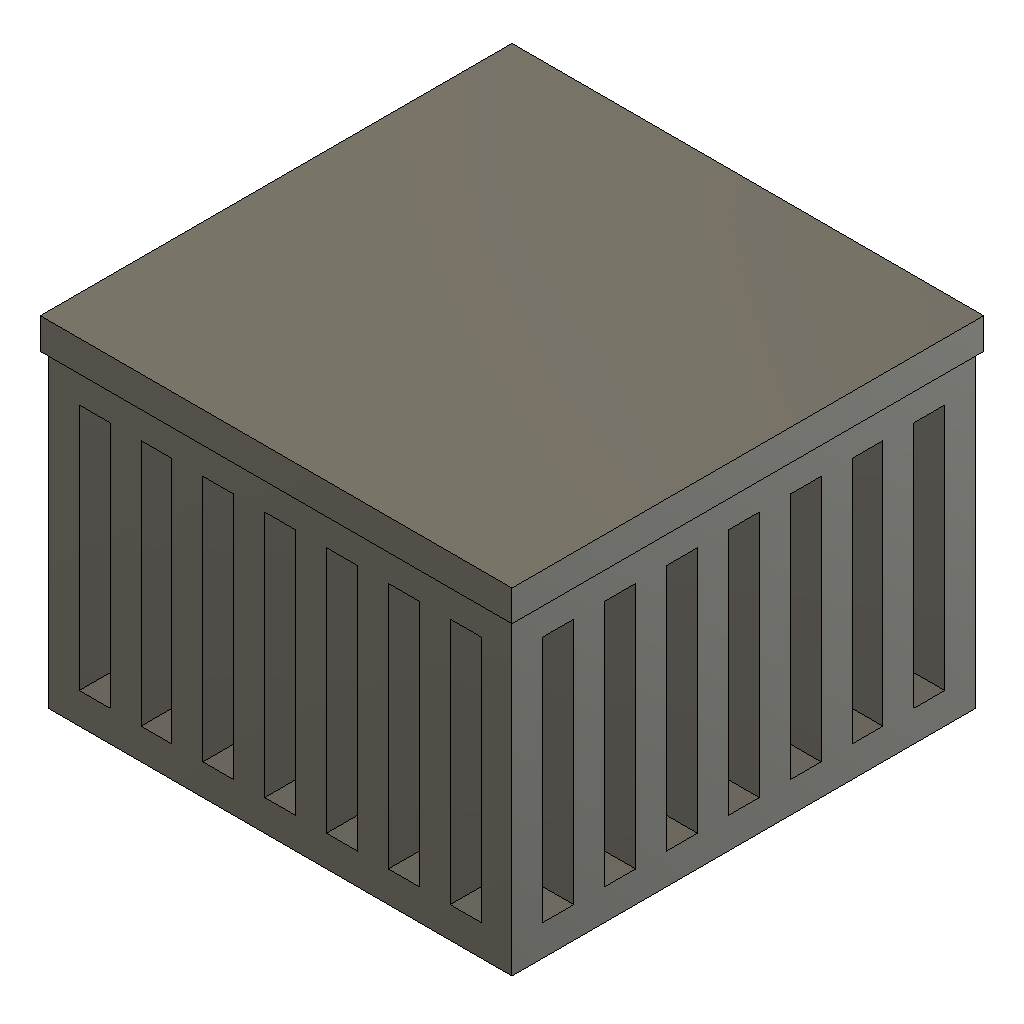
box (Autodesk Fusion 360 design; units mm, degrees)
part number: 2026-11-11-17-09-07-417
Autodesk Fusion 360 part; units mm, degrees
sketch "Sketch1" plane through (0, 0, 0) normal (0, 1, 0) x (1, 0, 0)
  line L0 (0, 0) -> (-150, 0)
  line L1 (-150, 0) -> (-150, 150)
  line L2 (-150, 150) -> (0, 150)
  line L3 (0, 150) -> (0, 0)
  dimension "d1" = 150
  dimension "d2" = 150
  constraint horizontal L0
  constraint vertical L1
  constraint horizontal L2
  constraint vertical L3
  constraint coincident L0.start L3.end
  measures "d1" distance of L0.start L0.end
  measures "d2" distance of L0.start L2.end
extrude "Extrude1" add sketch "Sketch1" along normal blind 100 makes body 1
sketch "Sketch2" plane through (0, 0, -150) normal (0, 0, -1) x (-1, 0, 0)
  line L0 (0, 0) -> (150, 0)
  line L1 (150, 0) -> (150, 100)
  line L2 (150, 100) -> (0, 100)
  line L3 (0, 100) -> (0, 0)
  line L4 (0, 100) -> (150, 100)
  line L5 (150, 100) -> (150, 0)
  line L6 (150, 0) -> (0, 0)
  line L7 (0, 0) -> (0, 100)
  line L8 (140, 10) -> (10, 10)
  line L9 (10, 10) -> (10, 90)
  line L10 (10, 90) -> (140, 90)
  line L11 (140, 90) -> (140, 10)
  line L12 (10, 90) -> (20, 90)
  line L13 (20, 90) -> (20, 10)
  line L14 (20, 10) -> (10, 10)
  line L15 (10, 10) -> (10, 90)
  constraint horizontal L4
  constraint vertical L5
  constraint horizontal L6
  constraint vertical L7
  constraint coincident L0.end L1.start
  constraint coincident L2.end L3.start
  constraint horizontal L8
  constraint vertical L9
  constraint horizontal L10
  constraint vertical L11
  constraint horizontal L12
  constraint vertical L13
  constraint horizontal L14
  constraint vertical L15
  constraint coincident L8 L13.end
extrude "Extrude2" add sketch "Sketch2" along normal blind 5 separate body contours L8 L9 L10 L12 L13 L14 L15 makes body 2
chamfer "Chamfer1" distance 5 angle 45 1 faces at (-13.3333, 36.6667, -155) tangent chain off on bodies 2
move_body "Move1" bodies 2 to x (-1, 0, 0) y (0, 1, 0) z (0, 0, -1) at (-30, 0, -310)
copy_body "CopyPasteBodies1" bodies 2 makes body 3
move_body "Move2" bodies 3 to x (1, 0, 0) y (0, 1, 0) z (0, 0, 1) at (-20, 0, 0)
copy_body "CopyPasteBodies2" bodies 2 3 makes body 4 makes body 5
move_body "Move3" bodies 4 5 to x (1, 0, 0) y (0, 1, 0) z (0, 0, 1) at (-40, 0, 0)
copy_body "CopyPasteBodies3" bodies 2 3 5 4 makes body 6 makes body 7 makes body 8 makes body 9
move_body "Move4" bodies 6 7 8 9 to x (1, 0, 0) y (0, 1, 0) z (0, 0, 1) at (-80, 0, 0)
delete_body "RemoveBody1" bodies 8
move_body "Move5" bodies 2 7 6 9 3 5 4 to x (1, 0, 0) y (0, 1, 0) z (0, 0, 1) at (0, 0, 10)
copy_body "CopyPasteBodies4" bodies 2 7 6 9 3 5 4 makes body 10 makes body 11 makes body 12 makes body 13 makes body 14 makes body 15 makes body 16
move_body "Move6" bodies 10 11 12 13 14 15 16 to x (0, 0, -1) y (0, 1, 0) z (1, 0, 0) at (0, 0, -150)
copy_body "CopyPasteBodies5" bodies 2 7 6 9 3 5 4 makes body 17 makes body 18 makes body 19 makes body 20 makes body 21 makes body 22 makes body 23
move_body "Move7" bodies 17 18 19 20 21 22 23 to x (-1, 0, 0) y (0, 1, 0) z (0, 0, -1) at (-150, 0, -150)
copy_body "CopyPasteBodies6" bodies 2 7 6 9 3 5 4 makes body 24 makes body 25 makes body 26 makes body 27 makes body 28 makes body 29 makes body 30
move_body "Move8" bodies 24 25 26 27 28 29 30 to x (0, 0, 1) y (0, 1, 0) z (-1, 0, 0) at (-150, 0, 0)
combine "Combine1" operation cut target body 1 tool bodies 2 5 3 4 10 11 13 12 14 6 7 9 19 20 22 15 16 18 21 17 24 25 26 23 28 29 27 30
sketch "Sketch3" plane through (0, 100, 0) normal (0, 1, 0) x (-1, 0, 0)
  line L0 (0, -150) -> (150, -150)
  line L1 (150, -150) -> (150, 0)
  line L2 (150, 0) -> (0, 0)
  line L3 (0, 0) -> (0, -150)
  line L4 (0, 0) -> (150, 0)
  line L5 (150, 0) -> (150, -150)
  line L6 (150, -150) -> (0, -150)
  line L7 (0, -150) -> (0, 0)
  line L8 (150.3, -150.3) -> (-0.3, -150.3)
  line L9 (-0.3, -150.3) -> (-0.3, 0.3)
  line L10 (-0.3, 0.3) -> (150.3, 0.3)
  line L11 (150.3, 0.3) -> (150.3, -150.3)
  line L12 (151.3, -151.3) -> (-1.3, -151.3)
  line L13 (-1.3, -151.3) -> (-1.3, 1.3)
  line L14 (-1.3, 1.3) -> (151.3, 1.3)
  line L15 (151.3, 1.3) -> (151.3, -151.3)
  dimension "d8" = -0.3
  dimension "d9" = -1
  constraint horizontal L4
  constraint vertical L5
  constraint horizontal L6
  constraint vertical L7
  constraint coincident L0.end L1.start
  constraint coincident L2.end L3.start
extrude "Extrude3" add sketch "Sketch3" along normal blind 10 separate body contours L0 L1 L2 L3 L4 L5 L6 L7 | L8 L9 L10 L11 | L12 L13 L14 L15 makes body 31
